caseCartStacked (Autodesk Fusion 360 design; units mm, degrees)
Autodesk Fusion 360 part; units mm, degrees
sketch "Sketch1" plane through (0, 0, 0) normal (0, 1, 0) x (1, 0, 0)
  circle A0 centre (0, 0) radius 5.625
  line L0 (0, 0) -> (5.625, 0)
  line L1 (5.625, 0) -> (7.625, 0)
  line L2 (7.625, 0) -> (13.25, 0)
  circle A1 centre (13.25, 0) radius 5.625
  line L3 (13.25, 0) -> (18.875, 0)
  line L4 (18.875, 0) -> (20.875, 0)
  line L5 (20.875, 0) -> (26.5, 0)
  circle A2 centre (26.5, 0) radius 5.625
  line L6 (0, 0) -> (-3.9775, 3.9775)
  line L7 (0, 0) -> (5.625, 0) construction
  line L8 (0, 0) -> (-5.625, 0)
  line L9 (0, 0) -> (-3.9775, -3.9775)
  line L10 (0, 0) -> (5.625, 0) construction
  line L11 (13.25, 0) -> (13.25, -5.625)
  line L12 (13.25, 0) -> (13.25, 5.625)
  line L13 (26.5, 0) -> (26.5, 5.625)
  line L14 (26.5, 0) -> (26.5, -5.625)
  line L15 (26.5, 0) -> (32.125, 0)
  line L16 (26.5, 0) -> (30.4775, 3.9775)
  line L17 (26.5, 0) -> (32.125, 0) construction
  line L18 (26.5, 0) -> (30.4775, -3.9775)
  line L19 (26.5, 0) -> (32.125, 0) construction
  line L20 (0, 0) -> (0, -5.625)
  line L21 (0, 0) -> (0, 5.625)
  line L22 (0, 5.625) -> (0, 7.225)
  line L23 (-3.9775, 3.9775) -> (-5.3917, 5.3917)
  line L24 (-5.625, 0) -> (-7.225, 0)
  line L25 (-3.9775, -3.9775) -> (-5.3917, -5.3917)
  line L26 (0, -5.625) -> (0, -7.225)
  line L27 (13.25, -5.625) -> (13.25, -7.625)
  line L28 (13.25, 5.625) -> (13.25, 7.625)
  line L29 (26.5, 5.625) -> (26.5, 7.225)
  line L30 (26.5, -5.625) -> (26.5, -7.225)
  line L31 (30.4775, -3.9775) -> (31.8917, -5.3917)
  line L32 (30.4775, 3.9775) -> (31.8917, 5.3917)
  line L33 (32.125, 0) -> (33.725, 0)
  line L34 (0, -7.225) -> (26.5, -7.225)
  line L35 (0, 7.225) -> (26.5, 7.225)
  arc A3 (0, 7.225) -> (0, -7.225) centre (0, 0) ccw
  arc A4 (26.5, -7.225) -> (26.5, 7.225) centre (26.5, 0) ccw
  dimension "d1" = 11.25
  dimension "d2" = 2
  dimension "d3" = 5.625
  dimension "d4" = 11.25
  dimension "d5" = 2
  dimension "d6" = 5.625
  dimension "d7" = 11.25
  dimension "d8" = 135
  dimension "d9" = 5.625
  dimension "d10" = 135
  dimension "d11" = 5.625
  dimension "d12" = 5.625
  dimension "d13" = 45
  dimension "d14" = 45
  dimension "d15" = 1.6
  dimension "d16" = 2
  dimension "d17" = 1.6
  dimension "d18" = 2
  dimension "d19" = 1.6
  dimension "d20" = 2
  dimension "d21" = 2
  dimension "d22" = 1.6
  dimension "d23" = 1.6
  dimension "d24" = 2
  dimension "d25" = 2
  dimension "d26" = 1.6
  constraint coincident A0.centre L0.start
  constraint coincident A0 L0.end
  constraint horizontal L0
  constraint parallel L0 L1
  constraint parallel L1 L2
  constraint coincident L2.end A1.centre
  constraint coincident A1 L3.end
  constraint parallel L2 L3
  constraint parallel L3 L4
  constraint horizontal L5
  constraint coincident L5.end A2.centre
  constraint horizontal L7
  constraint coincident A0 L8.end
  constraint parallel L7 L8
  constraint horizontal L10
  constraint perpendicular L3 L11
  constraint coincident A1 L12.end
  constraint perpendicular L3 L12
  constraint coincident A2 L13.end
  constraint perpendicular L5 L13
  constraint coincident A2 L14.end
  constraint perpendicular L5 L14
  constraint coincident A2 L15.end
  constraint perpendicular L14 L15
  constraint horizontal L17
  constraint horizontal L19
  constraint coincident A0 L20.end
  constraint perpendicular L7 L20
  constraint coincident A0 L21.end
  constraint perpendicular L7 L21
  constraint parallel L21 L22
  constraint parallel L6 L23
  constraint parallel L8 L24
  constraint parallel L9 L25
  constraint parallel L20 L26
  constraint parallel L11 L27
  constraint parallel L12 L28
  constraint parallel L13 L29
  constraint parallel L14 L30
  constraint parallel L18 L31
  constraint parallel L16 L32
  constraint parallel L17 L33
  constraint coincident L24.end A3
  constraint coincident L33.end A4
  measures "d1" diameter of A0
  measures "d2" distance of L0.end L1.end
  measures "d3" distance of L1.end L2.end
  measures "d4" diameter of A1
  measures "d5" distance of L3.end L4.end
  measures "d6" distance of L4.end L5.end
  measures "d7" diameter of A2
  measures "d8" angle of L6 L7
  measures "d9" distance of A0.centre L6.end
  measures "d10" angle of L9 L10
  measures "d11" distance of A0.centre L9.end
  measures "d12" distance of L2.end L11.end
  measures "d13" angle of L16 L17
  measures "d14" angle of L18 L19
  measures "d15" distance of L21.end L22.end
  measures "d16" distance of L6.end L23.end
  measures "d17" distance of L8.end L24.end
  measures "d18" distance of L9.end L25.end
  measures "d19" distance of L20.end L26.end
  measures "d20" distance of L11.end L27.end
  measures "d21" distance of L12.end L28.end
  measures "d22" distance of L13.end L29.end
  measures "d23" distance of L14.end L30.end
  measures "d24" distance of L18.end L31.end
  measures "d25" distance of L16.end L32.end
  measures "d26" distance of L15.end L33.end
extrude "Extrude1" add sketch "Sketch1" along normal blind 2 contours A0 L0 L21 | A0 L0 L20 | A0 L6 L21 | A0 L9 L20 | A0 L6 L8 | A0 L8 L9 | L2 A1 L12 | L2 A1 L11 | A1 L3 L12 | A1 L3 L11 | L5 A2 L13 | L5 A2 L14 | A2 L13 L16 | A2 L14 L18 | A2 L15 L16 | A2 L15 L18 makes body 1 at (-1.2523, 2, -0.4651) makes body 2 at (14.7646, 0, -1.518) makes body 3 at (26.3599, 0, -0.6809)
extrude "Extrude2" add sketch "Sketch1" along normal blind 44 contours A0 L1 A1 L26 L27 L34 | A0 L1 A1 L22 L28 L35 | A0 L22 L23 A3 | A0 L25 L26 A3 | A0 L23 L24 A3 | A0 L24 L25 A3 | A1 L4 A2 L28 L29 L35 | A1 L4 A2 L27 L30 L34 | A2 L29 L32 A4 | A2 L30 L31 A4 | A2 L32 L33 A4 | A2 L31 L33 A4 bodies 1 2 3
